Autodesk Fusion 360 part; units mm, degrees
(part 2 of 2)
sketch "Display controller PCB envelope" plane through (0, 0, 5) normal (0, 0, 1) x (1, 0, 0) in component "REF Waveshare module 76.54 x 74.66 - thickness provisional"
  line L0 (29.23, 83.67) -> (105.77, 83.67)
  line L1 (105.77, 83.67) -> (105.77, 158.33)
  line L2 (105.77, 158.33) -> (29.23, 158.33)
  line L3 (29.23, 158.33) -> (29.23, 83.67)
extrude "Display controller PCB envelope (1)" add sketch "Display controller PCB envelope" along normal blind 1.6 separate body makes body 16 in component "REF Waveshare module 76.54 x 74.66 - thickness provisional"
ref_plane "WorkPlane2" through (0, 0, 6.6) normal (0, 0, 1) x (1, 0, 0) in component "REF Waveshare module 76.54 x 74.66 - thickness provisional"
sketch "ESP32 and component clearance - illustrative" plane through (0, 0, 6.6) normal (0, 0, 1) x (1, 0, 0) in component "REF Waveshare module 76.54 x 74.66 - thickness provisional"
  line L0 (42, 100) -> (75, 100)
  line L1 (75, 100) -> (75, 127)
  line L2 (75, 127) -> (42, 127)
  line L3 (42, 127) -> (42, 100)
extrude "ESP32 and component clearance - illustrative (1)" add sketch "ESP32 and component clearance - illustrative" along normal blind 6.4 separate body makes body 17 in component "REF Waveshare module 76.54 x 74.66 - thickness provisional"
ref_plane "WorkPlane3" through (0, 0, 6.6) normal (0, 0, 1) x (1, 0, 0) in component "REF Waveshare module 76.54 x 74.66 - thickness provisional"
sketch "External connector clearance - verify board" plane through (0, 0, 6.6) normal (0, 0, 1) x (1, 0, 0) in component "REF Waveshare module 76.54 x 74.66 - thickness provisional"
  line L0 (87, 94) -> (105, 94)
  line L1 (105, 94) -> (105, 108)
  line L2 (105, 108) -> (87, 108)
  line L3 (87, 108) -> (87, 94)
extrude "External connector clearance - verify board (1)" add sketch "External connector clearance - verify board" along normal blind 7.4 separate body makes body 18 in component "REF Waveshare module 76.54 x 74.66 - thickness provisional"
ref_plane "WorkPlane4" through (0, 0, 6.6) normal (0, 0, 1) x (1, 0, 0) in component "REF Waveshare module 76.54 x 74.66 - thickness provisional"
sketch "WiFi antenna keep clear - location provisional" plane through (0, 0, 6.6) normal (0, 0, 1) x (1, 0, 0) in component "REF Waveshare module 76.54 x 74.66 - thickness provisional"
  line L0 (35, 148) -> (53, 148)
  line L1 (53, 148) -> (53, 157)
  line L2 (53, 157) -> (35, 157)
  line L3 (35, 157) -> (35, 148)
extrude "WiFi antenna keep clear - location provisional (1)" add sketch "WiFi antenna keep clear - location provisional" along normal blind 5 separate body makes body 19 in component "REF Waveshare module 76.54 x 74.66 - thickness provisional"
ref_plane "WorkPlane1" through (0, 0, 20) normal (0, 0, 1) x (1, 0, 0) in component "E01 Seesaw 4991 behind SELECT encoder"
sketch "4991 published PCB outline" plane through (0, 0, 20) normal (0, 0, 1) x (1, 0, 0) in component "E01 Seesaw 4991 behind SELECT encoder"
  line L0 (23.2, 23.35) -> (48.8, 23.35)
  line L1 (48.8, 23.35) -> (48.8, 48.65)
  line L2 (48.8, 48.65) -> (23.2, 48.65)
  line L3 (23.2, 48.65) -> (23.2, 23.35)
extrude "4991 published PCB outline (1)" add sketch "4991 published PCB outline" along normal blind 1.6 separate body makes body 20 in component "E01 Seesaw 4991 behind SELECT encoder"
ref_plane "WorkPlane2" through (0, 0, 21.6) normal (0, 0, 1) x (1, 0, 0) in component "E01 Seesaw 4991 behind SELECT encoder"
sketch "Seesaw component envelope" plane through (0, 0, 21.6) normal (0, 0, 1) x (1, 0, 0) in component "E01 Seesaw 4991 behind SELECT encoder"
  line L0 (27, 27) -> (35, 27)
  line L1 (35, 27) -> (35, 35)
  line L2 (35, 35) -> (27, 35)
  line L3 (27, 35) -> (27, 27)
extrude "Seesaw component envelope (1)" add sketch "Seesaw component envelope" along normal blind 3 separate body makes body 21 in component "E01 Seesaw 4991 behind SELECT encoder"
ref_plane "WorkPlane1" through (0, 0, 3) normal (0, 0, 1) x (1, 0, 0) in component "E02 Panel encoder body"
sketch "Encoder body envelope - select actual part" plane through (0, 0, 3) normal (0, 0, 1) x (1, 0, 0) in component "E02 Panel encoder body"
  line L0 (29.5, 29.5) -> (42.5, 29.5)
  line L1 (42.5, 29.5) -> (42.5, 42.5)
  line L2 (42.5, 42.5) -> (29.5, 42.5)
  line L3 (29.5, 42.5) -> (29.5, 29.5)
extrude "Encoder body envelope - select actual part (1)" add sketch "Encoder body envelope - select actual part" along normal blind 17 separate body makes body 22 in component "E02 Panel encoder body"
ref_plane "WorkPlane1" through (0, 0, 3) normal (0, 0, 1) x (1, 0, 0) in component "E03 B10K potentiometer body"
sketch "Pot body envelope - select actual part" plane through (0, 0, 3) normal (0, 0, 1) x (1, 0, 0) in component "E03 B10K potentiometer body"
  circle A0 centre (99, 36) radius 8.5
extrude "Pot body envelope - select actual part (1)" add sketch "Pot body envelope - select actual part" along normal blind 17 separate body makes body 23 in component "E03 B10K potentiometer body"
ref_plane "WorkPlane1" through (0, 0, 3) normal (0, 0, 1) x (1, 0, 0) in component "E04 HOLD switch body"
sketch "Panel toggle body envelope" plane through (0, 0, 3) normal (0, 0, 1) x (1, 0, 0) in component "E04 HOLD switch body"
  line L0 (13, 64) -> (23, 64)
  line L1 (23, 64) -> (23, 76)
  line L2 (23, 76) -> (13, 76)
  line L3 (13, 76) -> (13, 64)
extrude "Panel toggle body envelope (1)" add sketch "Panel toggle body envelope" along normal blind 17 separate body makes body 24 in component "E04 HOLD switch body"
ref_plane "WorkPlane1" through (0, 0, 3) normal (0, 0, 1) x (1, 0, 0) in component "E05 GRID switch body"
sketch "Panel toggle body envelope (2)" plane through (0, 0, 3) normal (0, 0, 1) x (1, 0, 0) in component "E05 GRID switch body"
  line L0 (112, 64) -> (122, 64)
  line L1 (122, 64) -> (122, 76)
  line L2 (122, 76) -> (112, 76)
  line L3 (112, 76) -> (112, 64)
extrude "Panel toggle body envelope (1)'" add sketch "Panel toggle body envelope (2)" along normal blind 17 separate body makes body 25 in component "E05 GRID switch body"
ref_plane "WorkPlane1" through (0, 0, 64) normal (0, 0, 1) x (1, 0, 0) in component "E06 MCP23017 5346 on removable tray"
sketch "5346 published PCB outline" plane through (0, 0, 64) normal (0, 0, 1) x (1, 0, 0) in component "E06 MCP23017 5346 on removable tray"
  line L0 (28, 24) -> (71, 24)
  line L1 (71, 24) -> (71, 42)
  line L2 (71, 42) -> (28, 42)
  line L3 (28, 42) -> (28, 24)
extrude "5346 published PCB outline (1)" add sketch "5346 published PCB outline" along normal blind 1.6 separate body makes body 26 in component "E06 MCP23017 5346 on removable tray"
ref_plane "WorkPlane2" through (0, 0, 65.6) normal (0, 0, 1) x (1, 0, 0) in component "E06 MCP23017 5346 on removable tray"
sketch "MCP component envelope" plane through (0, 0, 65.6) normal (0, 0, 1) x (1, 0, 0) in component "E06 MCP23017 5346 on removable tray"
  line L0 (38, 29) -> (50, 29)
  line L1 (50, 29) -> (50, 37)
  line L2 (50, 37) -> (38, 37)
  line L3 (38, 37) -> (38, 29)
extrude "MCP component envelope (1)" add sketch "MCP component envelope" along normal blind 3.4 separate body makes body 27 in component "E06 MCP23017 5346 on removable tray"
ref_plane "WorkPlane1" through (0, 0, 64) normal (0, 0, 1) x (1, 0, 0) in component "E07 ADS1115 1085 on removable tray"
sketch "1085 published PCB outline" plane through (0, 0, 64) normal (0, 0, 1) x (1, 0, 0) in component "E07 ADS1115 1085 on removable tray"
  line L0 (82, 24) -> (107.4, 24)
  line L1 (107.4, 24) -> (107.4, 41.8)
  line L2 (107.4, 41.8) -> (82, 41.8)
  line L3 (82, 41.8) -> (82, 24)
extrude "1085 published PCB outline (1)" add sketch "1085 published PCB outline" along normal blind 1.6 separate body makes body 28 in component "E07 ADS1115 1085 on removable tray"
ref_plane "WorkPlane2" through (0, 0, 65.6) normal (0, 0, 1) x (1, 0, 0) in component "E07 ADS1115 1085 on removable tray"
sketch "ADC component envelope" plane through (0, 0, 65.6) normal (0, 0, 1) x (1, 0, 0) in component "E07 ADS1115 1085 on removable tray"
  line L0 (91, 29) -> (97, 29)
  line L1 (97, 29) -> (97, 35)
  line L2 (97, 35) -> (91, 35)
  line L3 (91, 35) -> (91, 29)
extrude "ADC component envelope (1)" add sketch "ADC component envelope" along normal blind 3 separate body makes body 29 in component "E07 ADS1115 1085 on removable tray"
ref_plane "WorkPlane1" through (0, 0, 64) normal (0, 0, 1) x (1, 0, 0) in component "E08 Harness terminal perfboard"
sketch "Cut-to-size perfboard" plane through (0, 0, 64) normal (0, 0, 1) x (1, 0, 0) in component "E08 Harness terminal perfboard"
  line L0 (29, 53) -> (101, 53)
  line L1 (101, 53) -> (101, 73)
  line L2 (101, 73) -> (29, 73)
  line L3 (29, 73) -> (29, 53)
extrude "Cut-to-size perfboard (1)" add sketch "Cut-to-size perfboard" along normal blind 1.6 separate body makes body 30 in component "E08 Harness terminal perfboard"
ref_plane "WorkPlane2" through (0, 0, 65.6) normal (0, 0, 1) x (1, 0, 0) in component "E08 Harness terminal perfboard"
sketch "Detachable harness terminals" plane through (0, 0, 65.6) normal (0, 0, 1) x (1, 0, 0) in component "E08 Harness terminal perfboard"
  line L0 (35, 58) -> (90, 58)
  line L1 (90, 58) -> (90, 68)
  line L2 (90, 68) -> (35, 68)
  line L3 (35, 68) -> (35, 58)
extrude "Detachable harness terminals (1)" add sketch "Detachable harness terminals" along normal blind 8 separate body makes body 31 in component "E08 Harness terminal perfboard"
ref_plane "WorkPlane1" through (0, 0, 58) normal (0, 0, 1) x (1, 0, 0) in component "H01 Nylon 6mm board spacers - adjust to holes"
sketch "Nylon board spacer" plane through (0, 0, 58) normal (0, 0, 1) x (1, 0, 0) in component "H01 Nylon 6mm board spacers - adjust to holes"
  circle A0 centre (30, 26.5) radius 2.4
extrude "Nylon board spacer (1)" add sketch "Nylon board spacer" along normal blind 6 separate body makes body 32 in component "H01 Nylon 6mm board spacers - adjust to holes"
ref_plane "WorkPlane2" through (0, 0, 58) normal (0, 0, 1) x (1, 0, 0) in component "H01 Nylon 6mm board spacers - adjust to holes"
sketch "Nylon board spacer (1)" plane through (0, 0, 58) normal (0, 0, 1) x (1, 0, 0) in component "H01 Nylon 6mm board spacers - adjust to holes"
  circle A0 centre (68.5, 39.5) radius 2.4
extrude "Nylon board spacer (2)" add sketch "Nylon board spacer (1)" along normal blind 6 separate body makes body 33 in component "H01 Nylon 6mm board spacers - adjust to holes"
ref_plane "WorkPlane3" through (0, 0, 58) normal (0, 0, 1) x (1, 0, 0) in component "H01 Nylon 6mm board spacers - adjust to holes"
sketch "Nylon board spacer (2)" plane through (0, 0, 58) normal (0, 0, 1) x (1, 0, 0) in component "H01 Nylon 6mm board spacers - adjust to holes"
  circle A0 centre (84, 26.5) radius 2.4
extrude "Nylon board spacer (3)" add sketch "Nylon board spacer (2)" along normal blind 6 separate body makes body 34 in component "H01 Nylon 6mm board spacers - adjust to holes"
ref_plane "WorkPlane4" through (0, 0, 58) normal (0, 0, 1) x (1, 0, 0) in component "H01 Nylon 6mm board spacers - adjust to holes"
sketch "Nylon board spacer (3)" plane through (0, 0, 58) normal (0, 0, 1) x (1, 0, 0) in component "H01 Nylon 6mm board spacers - adjust to holes"
  circle A0 centre (104.9, 39.5) radius 2.4
extrude "Nylon board spacer (4)" add sketch "Nylon board spacer (3)" along normal blind 6 separate body makes body 35 in component "H01 Nylon 6mm board spacers - adjust to holes"
ref_plane "WorkPlane5" through (0, 0, 58) normal (0, 0, 1) x (1, 0, 0) in component "H01 Nylon 6mm board spacers - adjust to holes"
sketch "Nylon board spacer (4)" plane through (0, 0, 58) normal (0, 0, 1) x (1, 0, 0) in component "H01 Nylon 6mm board spacers - adjust to holes"
  circle A0 centre (32, 56) radius 2.4
extrude "Nylon board spacer (5)" add sketch "Nylon board spacer (4)" along normal blind 6 separate body makes body 36 in component "H01 Nylon 6mm board spacers - adjust to holes"
ref_plane "WorkPlane6" through (0, 0, 58) normal (0, 0, 1) x (1, 0, 0) in component "H01 Nylon 6mm board spacers - adjust to holes"
sketch "Nylon board spacer (5)" plane through (0, 0, 58) normal (0, 0, 1) x (1, 0, 0) in component "H01 Nylon 6mm board spacers - adjust to holes"
  circle A0 centre (98, 70) radius 2.4
extrude "Nylon board spacer (6)" add sketch "Nylon board spacer (5)" along normal blind 6 separate body makes body 37 in component "H01 Nylon 6mm board spacers - adjust to holes"
ref_plane "WorkPlane1" through (0, 0, 50) normal (0, 0, 1) x (1, 0, 0) in component "H02 Tray M3 screws and heat inserts"
sketch "M3 brass heat insert envelope" plane through (0, 0, 50) normal (0, 0, 1) x (1, 0, 0) in component "H02 Tray M3 screws and heat inserts"
  circle A0 centre (17.5, 20) radius 2.15
extrude "M3 brass heat insert envelope (1)" add sketch "M3 brass heat insert envelope" along normal blind 5 separate body makes body 38 in component "H02 Tray M3 screws and heat inserts"
ref_plane "WorkPlane2" through (0, 0, 52) normal (0, 0, 1) x (1, 0, 0) in component "H02 Tray M3 screws and heat inserts"
sketch "M3 screw shaft" plane through (0, 0, 52) normal (0, 0, 1) x (1, 0, 0) in component "H02 Tray M3 screws and heat inserts"
  circle A0 centre (17.5, 20) radius 1.5
extrude "M3 screw shaft (1)" add sketch "M3 screw shaft" along normal blind 6 separate body makes body 39 in component "H02 Tray M3 screws and heat inserts"
ref_plane "WorkPlane3" through (0, 0, 58) normal (0, 0, 1) x (1, 0, 0) in component "H02 Tray M3 screws and heat inserts"
sketch "M3 screw head" plane through (0, 0, 58) normal (0, 0, 1) x (1, 0, 0) in component "H02 Tray M3 screws and heat inserts"
  circle A0 centre (17.5, 20) radius 2.7
extrude "M3 screw head (1)" add sketch "M3 screw head" along normal blind 2 separate body makes body 40 in component "H02 Tray M3 screws and heat inserts"
ref_plane "WorkPlane4" through (0, 0, 50) normal (0, 0, 1) x (1, 0, 0) in component "H02 Tray M3 screws and heat inserts"
sketch "M3 brass heat insert envelope (1)" plane through (0, 0, 50) normal (0, 0, 1) x (1, 0, 0) in component "H02 Tray M3 screws and heat inserts"
  circle A0 centre (17.5, 70) radius 2.15
extrude "M3 brass heat insert envelope (2)" add sketch "M3 brass heat insert envelope (1)" along normal blind 5 separate body makes body 41 in component "H02 Tray M3 screws and heat inserts"
ref_plane "WorkPlane5" through (0, 0, 52) normal (0, 0, 1) x (1, 0, 0) in component "H02 Tray M3 screws and heat inserts"
sketch "M3 screw shaft (1)" plane through (0, 0, 52) normal (0, 0, 1) x (1, 0, 0) in component "H02 Tray M3 screws and heat inserts"
  circle A0 centre (17.5, 70) radius 1.5
extrude "M3 screw shaft (2)" add sketch "M3 screw shaft (1)" along normal blind 6 separate body makes body 42 in component "H02 Tray M3 screws and heat inserts"
ref_plane "WorkPlane6" through (0, 0, 58) normal (0, 0, 1) x (1, 0, 0) in component "H02 Tray M3 screws and heat inserts"
sketch "M3 screw head (1)" plane through (0, 0, 58) normal (0, 0, 1) x (1, 0, 0) in component "H02 Tray M3 screws and heat inserts"
  circle A0 centre (17.5, 70) radius 2.7
extrude "M3 screw head (2)" add sketch "M3 screw head (1)" along normal blind 2 separate body makes body 43 in component "H02 Tray M3 screws and heat inserts"
ref_plane "WorkPlane7" through (0, 0, 50) normal (0, 0, 1) x (1, 0, 0) in component "H02 Tray M3 screws and heat inserts"
sketch "M3 brass heat insert envelope (2)" plane through (0, 0, 50) normal (0, 0, 1) x (1, 0, 0) in component "H02 Tray M3 screws and heat inserts"
  circle A0 centre (117.5, 20) radius 2.15
extrude "M3 brass heat insert envelope (3)" add sketch "M3 brass heat insert envelope (2)" along normal blind 5 separate body makes body 44 in component "H02 Tray M3 screws and heat inserts"
ref_plane "WorkPlane8" through (0, 0, 52) normal (0, 0, 1) x (1, 0, 0) in component "H02 Tray M3 screws and heat inserts"
sketch "M3 screw shaft (2)" plane through (0, 0, 52) normal (0, 0, 1) x (1, 0, 0) in component "H02 Tray M3 screws and heat inserts"
  circle A0 centre (117.5, 20) radius 1.5
extrude "M3 screw shaft (3)" add sketch "M3 screw shaft (2)" along normal blind 6 separate body makes body 45 in component "H02 Tray M3 screws and heat inserts"
ref_plane "WorkPlane9" through (0, 0, 58) normal (0, 0, 1) x (1, 0, 0) in component "H02 Tray M3 screws and heat inserts"
sketch "M3 screw head (2)" plane through (0, 0, 58) normal (0, 0, 1) x (1, 0, 0) in component "H02 Tray M3 screws and heat inserts"
  circle A0 centre (117.5, 20) radius 2.7
extrude "M3 screw head (3)" add sketch "M3 screw head (2)" along normal blind 2 separate body makes body 46 in component "H02 Tray M3 screws and heat inserts"
ref_plane "WorkPlane10" through (0, 0, 50) normal (0, 0, 1) x (1, 0, 0) in component "H02 Tray M3 screws and heat inserts"
sketch "M3 brass heat insert envelope (3)" plane through (0, 0, 50) normal (0, 0, 1) x (1, 0, 0) in component "H02 Tray M3 screws and heat inserts"
  circle A0 centre (117.5, 70) radius 2.15
extrude "M3 brass heat insert envelope (4)" add sketch "M3 brass heat insert envelope (3)" along normal blind 5 separate body makes body 47 in component "H02 Tray M3 screws and heat inserts"
ref_plane "WorkPlane11" through (0, 0, 52) normal (0, 0, 1) x (1, 0, 0) in component "H02 Tray M3 screws and heat inserts"
sketch "M3 screw shaft (3)" plane through (0, 0, 52) normal (0, 0, 1) x (1, 0, 0) in component "H02 Tray M3 screws and heat inserts"
  circle A0 centre (117.5, 70) radius 1.5
extrude "M3 screw shaft (4)" add sketch "M3 screw shaft (3)" along normal blind 6 separate body makes body 48 in component "H02 Tray M3 screws and heat inserts"
ref_plane "WorkPlane12" through (0, 0, 58) normal (0, 0, 1) x (1, 0, 0) in component "H02 Tray M3 screws and heat inserts"
sketch "M3 screw head (3)" plane through (0, 0, 58) normal (0, 0, 1) x (1, 0, 0) in component "H02 Tray M3 screws and heat inserts"
  circle A0 centre (117.5, 70) radius 2.7
extrude "M3 screw head (4)" add sketch "M3 screw head (3)" along normal blind 2 separate body makes body 49 in component "H02 Tray M3 screws and heat inserts"
ref_plane "WorkPlane1" through (0, 0, 35) normal (0, 0, 1) x (1, 0, 0) in component "W01 Four-wire I2C route envelope - blue"
sketch "Vertical harness corridor" plane through (0, 0, 35) normal (0, 0, 1) x (1, 0, 0) in component "W01 Four-wire I2C route envelope - blue"
  line L0 (112, 25) -> (115, 25)
  line L1 (115, 25) -> (115, 111)
  line L2 (115, 111) -> (112, 111)
  line L3 (112, 111) -> (112, 25)
extrude "Vertical harness corridor (1)" add sketch "Vertical harness corridor" along normal blind 3 separate body makes body 50 in component "W01 Four-wire I2C route envelope - blue"
ref_plane "WorkPlane2" through (0, 0, 35) normal (0, 0, 1) x (1, 0, 0) in component "W01 Four-wire I2C route envelope - blue"
sketch "Display I2C branch" plane through (0, 0, 35) normal (0, 0, 1) x (1, 0, 0) in component "W01 Four-wire I2C route envelope - blue"
  line L0 (101, 106) -> (112, 106)
  line L1 (112, 106) -> (112, 109)
  line L2 (112, 109) -> (101, 109)
  line L3 (101, 109) -> (101, 106)
extrude "Display I2C branch (1)" add sketch "Display I2C branch" along normal blind 3 separate body makes body 51 in component "W01 Four-wire I2C route envelope - blue"
ref_plane "WorkPlane3" through (0, 0, 35) normal (0, 0, 1) x (1, 0, 0) in component "W01 Four-wire I2C route envelope - blue"
sketch "Tray harness branch" plane through (0, 0, 35) normal (0, 0, 1) x (1, 0, 0) in component "W01 Four-wire I2C route envelope - blue"
  line L0 (107, 33) -> (112, 33)
  line L1 (112, 33) -> (112, 36)
  line L2 (112, 36) -> (107, 36)
  line L3 (107, 36) -> (107, 33)
extrude "Tray harness branch (1)" add sketch "Tray harness branch" along normal blind 29 separate body makes body 52 in component "W01 Four-wire I2C route envelope - blue"
ref_plane "WorkPlane4" through (0, 0, 25) normal (0, 0, 1) x (1, 0, 0) in component "W01 Four-wire I2C route envelope - blue"
sketch "Encoder harness branch" plane through (0, 0, 25) normal (0, 0, 1) x (1, 0, 0) in component "W01 Four-wire I2C route envelope - blue"
  line L0 (46, 43) -> (112, 43)
  line L1 (112, 43) -> (112, 46)
  line L2 (112, 46) -> (46, 46)
  line L3 (46, 46) -> (46, 43)
extrude "Encoder harness branch (1)" add sketch "Encoder harness branch" along normal blind 3 separate body makes body 53 in component "W01 Four-wire I2C route envelope - blue"
ref_plane "WorkPlane1" through (0, 0, 16) normal (0, 0, 1) x (1, 0, 0) in component "W02 USB power route envelope - orange"
sketch "Display USB service loop corridor" plane through (0, 0, 16) normal (0, 0, 1) x (1, 0, 0) in component "W02 USB power route envelope - orange"
  line L0 (102, 113) -> (106, 113)
  line L1 (106, 113) -> (106, 117)
  line L2 (106, 117) -> (102, 117)
  line L3 (102, 117) -> (102, 113)
extrude "Display USB service loop corridor (1)" add sketch "Display USB service loop corridor" along normal blind 58 separate body makes body 54 in component "W02 USB power route envelope - orange"
ref_plane "WorkPlane2" through (0, 0, 74) normal (0, 0, 1) x (1, 0, 0) in component "W02 USB power route envelope - orange"
sketch "USB rear route horizontal" plane through (0, 0, 74) normal (0, 0, 1) x (1, 0, 0) in component "W02 USB power route envelope - orange"
  line L0 (67, 21) -> (106, 21)
  line L1 (106, 21) -> (106, 25)
  line L2 (106, 25) -> (67, 25)
  line L3 (67, 25) -> (67, 21)
extrude "USB rear route horizontal (1)" add sketch "USB rear route horizontal" along normal blind 4 separate body makes body 55 in component "W02 USB power route envelope - orange"
ref_plane "WorkPlane3" through (0, 0, 74) normal (0, 0, 1) x (1, 0, 0) in component "W02 USB power route envelope - orange"
sketch "USB rear route vertical" plane through (0, 0, 74) normal (0, 0, 1) x (1, 0, 0) in component "W02 USB power route envelope - orange"
  line L0 (102, 25) -> (106, 25)
  line L1 (106, 25) -> (106, 113)
  line L2 (106, 113) -> (102, 113)
  line L3 (102, 113) -> (102, 25)
extrude "USB rear route vertical (1)" add sketch "USB rear route vertical" along normal blind 4 separate body makes body 56 in component "W02 USB power route envelope - orange"
ref_plane "WorkPlane4" through (0, 0, 78) normal (0, 0, 1) x (1, 0, 0) in component "W02 USB power route envelope - orange"
sketch "Rear USB extension route" plane through (0, 0, 78) normal (0, 0, 1) x (1, 0, 0) in component "W02 USB power route envelope - orange"
  line L0 (64.5, 18) -> (70.5, 18)
  line L1 (70.5, 18) -> (70.5, 24)
  line L2 (70.5, 24) -> (64.5, 24)
  line L3 (64.5, 24) -> (64.5, 18)
extrude "Rear USB extension route (1)" add sketch "Rear USB extension route" along normal blind 14 separate body makes body 57 in component "W02 USB power route envelope - orange"
ref_plane "WorkPlane1" through (0, 0, 83) normal (0, 0, 1) x (1, 0, 0) in component "E09 Panel USB extension - generic envelope"
sketch "Bolted USB extension envelope - verify chosen part" plane through (0, 0, 83) normal (0, 0, 1) x (1, 0, 0) in component "E09 Panel USB extension - generic envelope"
  line L0 (52, 13.5) -> (83, 13.5)
  line L1 (83, 13.5) -> (83, 28.5)
  line L2 (83, 28.5) -> (52, 28.5)
  line L3 (52, 28.5) -> (52, 13.5)
extrude "Bolted USB extension envelope - verify chosen part (1)" add sketch "Bolted USB extension envelope - verify chosen part" along normal blind 9 separate body makes body 58 in component "E09 Panel USB extension - generic envelope"
ref_plane "WorkPlane24" through (0, 0, 3) normal (0, 0, 1) x (1, 0, 0) in component "01 Ivory front panel"
sketch "Sketch24" plane through (0, 0, 3) normal (0, 0, 1) x (1, 0, 0) in component "01 Ivory front panel"
  line L0 (29.5, 96) -> (30.5, 96)
  line L1 (30.5, 96) -> (30.5, 116)
  line L2 (30.5, 116) -> (29.5, 116)
  line L3 (29.5, 116) -> (29.5, 96)
extrude "PCB edge seating pad - verify glass offset" add sketch "Sketch24" along normal blind 2 bodies 1 in component "01 Ivory front panel"
ref_plane "WorkPlane8" through (0, 0, 7.1) normal (0, 0, 1) x (1, 0, 0) in component "06 Display rear retainer - fit prototype"
sketch "Sketch8" plane through (0, 0, 7.1) normal (0, 0, 1) x (1, 0, 0) in component "06 Display rear retainer - fit prototype"
  line L0 (29.5, 96) -> (30.5, 96)
  line L1 (30.5, 96) -> (30.5, 116)
  line L2 (30.5, 116) -> (29.5, 116)
  line L3 (29.5, 116) -> (29.5, 96)
extrude "PCB rear pressure pad - 0.5mm soft gasket gap" add sketch "Sketch8" along normal blind 9.9 bodies 6 in component "06 Display rear retainer - fit prototype"
ref_plane "WorkPlane25" through (0, 0, 3) normal (0, 0, 1) x (1, 0, 0) in component "01 Ivory front panel"
sketch "Sketch25" plane through (0, 0, 3) normal (0, 0, 1) x (1, 0, 0) in component "01 Ivory front panel"
  line L0 (104.5, 96) -> (105.5, 96)
  line L1 (105.5, 96) -> (105.5, 116)
  line L2 (105.5, 116) -> (104.5, 116)
  line L3 (104.5, 116) -> (104.5, 96)
extrude "PCB edge seating pad - verify glass offset (1)" add sketch "Sketch25" along normal blind 2 bodies 1 in component "01 Ivory front panel"
ref_plane "WorkPlane9" through (0, 0, 7.1) normal (0, 0, 1) x (1, 0, 0) in component "06 Display rear retainer - fit prototype"
sketch "Sketch9" plane through (0, 0, 7.1) normal (0, 0, 1) x (1, 0, 0) in component "06 Display rear retainer - fit prototype"
  line L0 (104.5, 96) -> (105.5, 96)
  line L1 (105.5, 96) -> (105.5, 116)
  line L2 (105.5, 116) -> (104.5, 116)
  line L3 (104.5, 116) -> (104.5, 96)
extrude "PCB rear pressure pad - 0.5mm soft gasket gap (1)" add sketch "Sketch9" along normal blind 9.9 bodies 6 in component "06 Display rear retainer - fit prototype"
ref_plane "WorkPlane1" through (0, 0, 95) normal (0, 0, 1) x (1, 0, 0) in component "07 Replaceable USB adapter - generic 24mm flange pitch"
sketch "Sketch1" plane through (0, 0, 95) normal (0, 0, 1) x (1, 0, 0) in component "07 Replaceable USB adapter - generic 24mm flange pitch"
  line L0 (43, 8) -> (92, 8)
  line L1 (92, 8) -> (92, 34)
  line L2 (92, 34) -> (43, 34)
  line L3 (43, 34) -> (43, 8)
extrude "USB adapter plate" add sketch "Sketch1" along normal blind 2 separate body makes body 59 in component "07 Replaceable USB adapter - generic 24mm flange pitch"
ref_plane "WorkPlane2" through (0, 0, 95) normal (0, 0, 1) x (1, 0, 0) in component "07 Replaceable USB adapter - generic 24mm flange pitch"
sketch "Sketch2" plane through (0, 0, 95) normal (0, 0, 1) x (1, 0, 0) in component "07 Replaceable USB adapter - generic 24mm flange pitch"
  line L0 (59.5, 16.5) -> (75.5, 16.5)
  line L1 (75.5, 16.5) -> (75.5, 25.5)
  line L2 (75.5, 25.5) -> (59.5, 25.5)
  line L3 (59.5, 25.5) -> (59.5, 16.5)
extrude "USB connector opening - verify selected extension" cut sketch "Sketch2" along normal blind 2 bodies 59 in component "07 Replaceable USB adapter - generic 24mm flange pitch"
ref_plane "WorkPlane3" through (0, 0, 95) normal (0, 0, 1) x (1, 0, 0) in component "07 Replaceable USB adapter - generic 24mm flange pitch"
sketch "Sketch3" plane through (0, 0, 95) normal (0, 0, 1) x (1, 0, 0) in component "07 Replaceable USB adapter - generic 24mm flange pitch"
  circle A0 centre (47.5, 21) radius 1.7
extrude "Adapter fixing" cut sketch "Sketch3" along normal blind 2 bodies 59 in component "07 Replaceable USB adapter - generic 24mm flange pitch"
ref_plane "WorkPlane15" through (0, 0, 92) normal (0, 0, 1) x (1, 0, 0) in component "03 Ivory rear cover"
sketch "Sketch15" plane through (0, 0, 92) normal (0, 0, 1) x (1, 0, 0) in component "03 Ivory rear cover"
  circle A0 centre (47.5, 21) radius 1.7
extrude "Adapter fixing'" cut sketch "Sketch15" along normal blind 3 bodies 3 in component "03 Ivory rear cover"
ref_plane "WorkPlane4" through (0, 0, 95) normal (0, 0, 1) x (1, 0, 0) in component "07 Replaceable USB adapter - generic 24mm flange pitch"
sketch "Sketch4" plane through (0, 0, 95) normal (0, 0, 1) x (1, 0, 0) in component "07 Replaceable USB adapter - generic 24mm flange pitch"
  circle A0 centre (87.5, 21) radius 1.7
extrude "Adapter fixing (1)" cut sketch "Sketch4" along normal blind 2 bodies 59 in component "07 Replaceable USB adapter - generic 24mm flange pitch"
ref_plane "WorkPlane16" through (0, 0, 92) normal (0, 0, 1) x (1, 0, 0) in component "03 Ivory rear cover"
sketch "Sketch16" plane through (0, 0, 92) normal (0, 0, 1) x (1, 0, 0) in component "03 Ivory rear cover"
  circle A0 centre (87.5, 21) radius 1.7
extrude "Adapter fixing (1)'" cut sketch "Sketch16" along normal blind 3 bodies 3 in component "03 Ivory rear cover"
ref_plane "WorkPlane5" through (0, 0, 95) normal (0, 0, 1) x (1, 0, 0) in component "07 Replaceable USB adapter - generic 24mm flange pitch"
sketch "Sketch5" plane through (0, 0, 95) normal (0, 0, 1) x (1, 0, 0) in component "07 Replaceable USB adapter - generic 24mm flange pitch"
  circle A0 centre (55.5, 21) radius 1.4
extrude "Adapter fixing (2)" cut sketch "Sketch5" along normal blind 2 bodies 59 in component "07 Replaceable USB adapter - generic 24mm flange pitch"
ref_plane "WorkPlane6" through (0, 0, 95) normal (0, 0, 1) x (1, 0, 0) in component "07 Replaceable USB adapter - generic 24mm flange pitch"
sketch "Sketch6" plane through (0, 0, 95) normal (0, 0, 1) x (1, 0, 0) in component "07 Replaceable USB adapter - generic 24mm flange pitch"
  circle A0 centre (79.5, 21) radius 1.4
extrude "Adapter fixing (3)" cut sketch "Sketch6" along normal blind 2 bodies 59 in component "07 Replaceable USB adapter - generic 24mm flange pitch"
component "01 Ivory front panel" placed x (1, 0, 0) y (0, 1, 0) z (0, 0, 1) at (0, 0, 0)
component "02 Ivory shell" placed x (1, 0, 0) y (0, 1, 0) z (0, 0, 1) at (0, 0, 0)
component "03 Ivory rear cover" placed x (1, 0, 0) y (0, 1, 0) z (0, 0, 1) at (0, 0, 0)
component "04 Charcoal bezel" placed x (1, 0, 0) y (0, 1, 0) z (0, 0, 1) at (0, 0, 0)
component "05 Internal removable control tray" placed x (1, 0, 0) y (0, 1, 0) z (0, 0, 1) at (0, 0, 0)
component "06 Display rear retainer - fit prototype" placed x (1, 0, 0) y (0, 1, 0) z (0, 0, 1) at (0, 0, 0)
component "REF Green TFT visible area" placed x (1, 0, 0) y (0, 1, 0) z (0, 0, 1) at (0, 0, 0)
component "REF Select knob" placed x (1, 0, 0) y (0, 1, 0) z (0, 0, 1) at (0, 0, 0)
component "REF Zoom knob" placed x (1, 0, 0) y (0, 1, 0) z (0, 0, 1) at (0, 0, 0)
component "REF HOLD toggle" placed x (1, 0, 0) y (0, 1, 0) z (0, 0, 1) at (0, 0, 0)
component "REF GRID toggle" placed x (1, 0, 0) y (0, 1, 0) z (0, 0, 1) at (0, 0, 0)
component "REF Waveshare module 76.54 x 74.66 - thickness provisional" placed x (1, 0, 0) y (0, 1, 0) z (0, 0, 1) at (0, 0, 0)
component "E01 Seesaw 4991 behind SELECT encoder" placed x (1, 0, 0) y (0, 1, 0) z (0, 0, 1) at (0, 0, 0)
component "E02 Panel encoder body" placed x (1, 0, 0) y (0, 1, 0) z (0, 0, 1) at (0, 0, 0)
component "E03 B10K potentiometer body" placed x (1, 0, 0) y (0, 1, 0) z (0, 0, 1) at (0, 0, 0)
component "E04 HOLD switch body" placed x (1, 0, 0) y (0, 1, 0) z (0, 0, 1) at (0, 0, 0)
component "E05 GRID switch body" placed x (1, 0, 0) y (0, 1, 0) z (0, 0, 1) at (0, 0, 0)
component "E06 MCP23017 5346 on removable tray" placed x (1, 0, 0) y (0, 1, 0) z (0, 0, 1) at (0, 0, 0)
component "E07 ADS1115 1085 on removable tray" placed x (1, 0, 0) y (0, 1, 0) z (0, 0, 1) at (0, 0, 0)
component "E08 Harness terminal perfboard" placed x (1, 0, 0) y (0, 1, 0) z (0, 0, 1) at (0, 0, 0)
component "H01 Nylon 6mm board spacers - adjust to holes" placed x (1, 0, 0) y (0, 1, 0) z (0, 0, 1) at (0, 0, 0)
component "H02 Tray M3 screws and heat inserts" placed x (1, 0, 0) y (0, 1, 0) z (0, 0, 1) at (0, 0, 0)
component "W01 Four-wire I2C route envelope - blue" placed x (1, 0, 0) y (0, 1, 0) z (0, 0, 1) at (0, 0, 0)
component "W02 USB power route envelope - orange" placed x (1, 0, 0) y (0, 1, 0) z (0, 0, 1) at (0, 0, 0)
component "E09 Panel USB extension - generic envelope" placed x (1, 0, 0) y (0, 1, 0) z (0, 0, 1) at (0, 0, 0)
component "07 Replaceable USB adapter - generic 24mm flange pitch" placed x (1, 0, 0) y (0, 1, 0) z (0, 0, 1) at (0, 0, 0)
